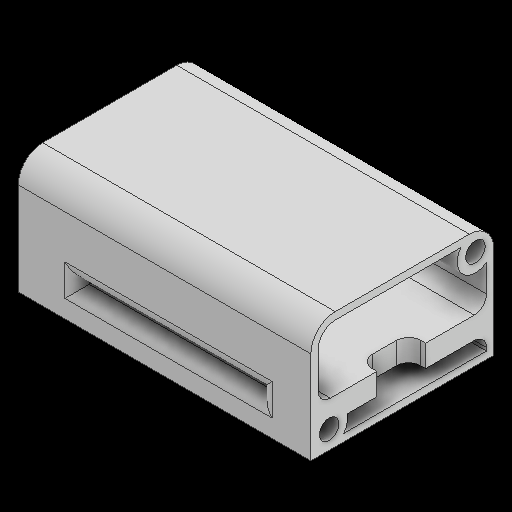
# Autodesk Inventor part: Gehäuse2
Saved by Autodesk Inventor 2027.1 (Build 311270010, 270A)
## iProperties
Created: 2026-10-15
Part Number: Gehäuse2
Material: Generisch
Document SubType Name: Modeling
Designer: josia
Density: 1 g/cm^3
Appearance: Vorgabe
Author: josia
Autodesk Inventor part; units mm, degrees
ref_plane "YZ Plane" through (0, 0, 0) normal (1, 0, 0) x (0, 1, 0)
ref_plane "XZ Plane" through (0, 0, 0) normal (0, 1, 0) x (-1, 0, 0)
ref_plane "XY Plane" through (0, 0, 0) normal (0, 0, 1) x (1, 0, 0)
sketch "Skizze1" plane through (0, 0, 0) normal (1, 0, 0) x (0, 1, 0)
  line L0 (-0.6, -15) -> (0.6, -15)
  line L1 (0.6, -15) -> (0.6, 15)
  line L2 (0.6, 15) -> (-0.6, 15)
  line L3 (-0.6, 15) -> (-0.6, -15)
  line L4 (-0.6, -15) -> (0.6, 15) construction
  line L5 (0.6, -15) -> (-0.6, 15) construction
  line L6 (0.6, 15) -> (14.6, 15)
  line L7 (18.6, 11) -> (18.6, 13.8)
  line L8 (18.6, 13.8) -> (0.6, 13.8)
  line L9 (0.6, 13.8) -> (0.6, 15)
  line L10 (0.6, -15) -> (14.6, -15)
  line L11 (18.6, -11) -> (18.6, -13.8)
  line L12 (18.6, -13.8) -> (0.6, -13.8)
  line L13 (0.6, -13.8) -> (0.6, -15)
  line L14 (18.6, 13.8) -> (17.4, 13.8)
  line L15 (17.4, 13.8) -> (17.4, -13.8)
  line L16 (17.4, -13.8) -> (18.6, -13.8)
  line L17 (18.6, -13.8) -> (18.6, 13.8)
  arc A0 (18.6, 11) -> (14.6, 15) centre (14.6, 11) ccw
  arc A1 (14.6, -15) -> (18.6, -11) centre (14.6, -11) ccw
  arc A2 (17.4, 11) -> (14.6, 13.8) centre (14.6, 11) ccw
  arc A3 (14.6, -13.8) -> (17.4, -11) centre (14.6, -11) ccw
  line L18 (0.6, 13.8) -> (3.1, 13.8)
  line L19 (3.1, 13.8) -> (3.1, -13.8)
  line L20 (3.1, -13.8) -> (0.6, -13.8)
  line L21 (0.6, -13.8) -> (0.6, 13.8)
  line L22 (3.1, 13.8) -> (6.7, 13.8)
  line L23 (6.7, 13.8) -> (6.7, -13.8)
  line L24 (6.7, -13.8) -> (3.1, -13.8)
  line L25 (3.1, -13.8) -> (3.1, 13.8)
  point P0 (0, 0)
  point P1 (18.6, 15)
  point P2 (18.6, -15)
  point P3 (0.6, -13.8)
  point P4 (0.6, 13.8)
  dimension "d0" = 1.2
  dimension "d1" = 30
  dimension "d2" = 18
  dimension "d3" = 1.2
  dimension "d4" = 18
  dimension "d5" = 1.2
  dimension "d6" = 1.2
  dimension "d7" = 4
  dimension "d8" = 4
  dimension "d9" = 2.5
  dimension "d10" = 3.6
  constraints: 52 end point, 12 parallel, 11 point on line, 8 point on circle, 8 tangent, 6 horizontal, 6 perpendicular, 4 centre point, 2 midpoint
  measures "d0" distance of L2.end L1.end
  measures "d1" distance of L1.end L0.end
  measures "d2" distance of L7.end L8.end
  measures "d3" distance of point (18.6, 15) L7.end
  measures "d4" distance of L12.end L11.end
  measures "d5" distance of L11.end point (18.6, -15)
  measures "d6" distance of L16.end L15.end
  measures "d7" radius of A0
  measures "d8" radius of A1
  measures "d9" distance of L19.end L20.end
  measures "d10" distance of L23.end L24.end
extrude "Extrusion1" add sketch "Skizze1" along normal blind 48 contours L3 L2 L1 L0 | L1 L12 A1 L10 | L6 A0 L8 L1 | L19 L8 L23 L12 | L12 L15 L8 A0 L17 A1 | L12 A3 L15 | L15 A2 L8
sketch "Skizze2" plane through (0, 0, 0) normal (-1, 0, 0) x (0, 0, 1)
  line L0 (-15, -0.6) -> (-15, 14.6) projected
  arc A0 (-11, 18.6) -> (-15, 14.6) centre (-11, 14.6) ccw projected
  line L1 (-11, 18.6) -> (11, 18.6) projected
  arc A1 (15, 14.6) -> (11, 18.6) centre (11, 14.6) ccw projected
  line L2 (15, 14.6) -> (15, -0.6) projected
  line L3 (15, -0.6) -> (-15, -0.6) projected
  point P0 (0, 0)
extrude "Extrusion2" add sketch "Skizze2" against normal blind 1.2
sketch "Skizze3" plane through (48, 0, 0) normal (1, 0, 0) x (0, 0, -1)
  line L0 (-13.8, 3.1) -> (13.8, 3.1) projected
  line L1 (13.8, 6.7) -> (-13.8, 6.7) projected
  line L2 (-4.1636, 3.1) -> (3.8364, 3.1)
  line L3 (3.8364, 3.1) -> (3.8364, 6.7)
  line L4 (3.8364, 6.7) -> (-4.1636, 6.7)
  line L5 (-4.1636, 6.7) -> (-4.1636, 3.1)
  point P0 (0, 0)
  dimension "d15" = 8
  constraints: 8 end point, 2 parallel, 2 point on line, 1 horizontal, 1 perpendicular
  measures "d15" distance of L4.end L3.end
extrude "Extrusion3" cut sketch "Skizze3" against normal blind 2.8
fillet "Rundung1" radius 2 2 edges at (45.2, 4.9, 4.1636) (45.2, 4.9, -3.8364)
sketch "Skizze4" plane through (0, -0.6, -15) normal (0, 0, -1) x (-1, 0, 0)
  line L0 (0, 0) -> (-48, 0) projected
  line L1 (0, 0) -> (0, 15.2) projected
  line L2 (-48, 0) -> (0, 0)
  line L3 (0, 0) -> (0, 4.9)
  line L4 (0, 4.9) -> (-48, 4.9)
  line L5 (-48, 4.9) -> (-48, 0)
  line L6 (-48, 4.9) -> (0, 4.9)
  line L7 (0, 4.9) -> (0, 6.1)
  line L8 (0, 6.1) -> (-48, 6.1)
  line L9 (-48, 6.1) -> (-48, 4.9)
  line L10 (-39.6501, 4.9) -> (-9.6501, 4.9)
  line L11 (-9.6501, 4.9) -> (-9.6501, 6.1)
  line L12 (-9.6501, 6.1) -> (-39.6501, 6.1)
  line L13 (-39.6501, 6.1) -> (-39.6501, 4.9)
  point P0 (0, 0.6)
  dimension "d19" = 4.9
  dimension "d20" = 1.2
  dimension "d21" = 30
  constraints: 24 end point, 6 parallel, 4 point on line, 3 horizontal, 3 perpendicular
  measures "d19" distance of L3.end L2.end
  measures "d20" distance of L7.end L6.end
  measures "d21" distance of L12.end L11.end
extrude "Extrusion4" cut sketch "Skizze4" against normal blind 52.7 contours L4 L13 L8 L11
fillet "Rundung2" radius 2 12 edges at (24.6501, 5.5, 15) (24.6501, 4.3, 15) (39.6501, 4.9, 15) (9.6501, 4.9, 15) (24.6501, 5.5, -15) (9.6501, 4.9, -15) (24.6501, 4.3, -15) (39.6501, 4.9, -15) (24.6, 3.1, -13.8) (24.6, 6.7, -13.8) (24.6, 6.7, 13.8) (24.6, 3.1, 13.8)
sketch "Skizze5" plane through (48, 0, 0) normal (1, 0, 0) x (0, 0, -1)
  line L0 (-15, -0.6) -> (15, -0.6) projected
  line L1 (-15, -0.6) -> (-12, -0.6)
  line L2 (-12, -0.6) -> (-12, 2.4)
  line L3 (-12, 2.4) -> (-15, 2.4)
  line L4 (-15, 2.4) -> (-15, -0.6)
  circle A0 centre (-12, 2.4) radius 3
  point P0 (0, 0)
  dimension "d25" = 3
  dimension "d26" = 3
  constraints: 8 end point, 2 parallel, 1 coincident, 1 horizontal, 1 horizontal alignment, 1 perpendicular, 2 other
  measures "d25" distance of L3.end L2.end
  measures "d26" distance of L2.end L1.end
extrude "Extrusion5" add sketch "Skizze5" against normal blind 4 contours A0 L3 L2 | L2 L3 A0
sketch "Skizze6" plane through (48, 0, 0) normal (1, 0, 0) x (0, 0, -1)
  line L0 (15, 18.6) -> (12, 18.6)
  line L1 (12, 18.6) -> (12, 15.6)
  line L2 (12, 15.6) -> (15, 15.6)
  line L3 (15, 15.6) -> (15, 18.6)
  circle A0 centre (12, 15.6) radius 3
  arc A1 (15, 14.6) -> (11, 18.6) centre (11, 14.6) ccw projected
  point P0 (0, 0)
  point P1 (11.5361, 18.5639)
  point P2 (14.9639, 15.1361)
  dimension "d29" = 3
  dimension "d30" = 3
  constraints: 8 end point, 2 parallel, 1 coincident, 1 horizontal, 1 perpendicular, 3 other
  measures "d29" distance of L2.end L1.end
  measures "d30" distance of L1.end L0.end
extrude "Extrusion6" add sketch "Skizze6" against normal blind 4 contours A1 L2 L1 | L1 L2 A1 A0 picked at (11.5596, 17.4909)
sketch "Skizze7" plane through (48, 0, 0) normal (1, 0, 0) x (0, 0, -1)
  arc A0 (-9.6, 0.6) -> (-9.0828, 3.1) centre (-12, 2.4) ccw projected
  circle A1 centre (-12, 2.4) radius 1.6
  arc A2 (9.6, 17.4) -> (13.8, 13.2) centre (12, 15.6) ccw projected
  circle A3 centre (12, 15.6) radius 1.6
  point P0 (0, 0)
  dimension "d33" = 3.2
  dimension "d34" = 3.2
  constraints: 2 centre point, 2 coincident
  measures "d33" diameter of A1
  measures "d34" diameter of A3
extrude "Extrusion7" cut sketch "Skizze7" against normal blind 2.5
sketch "Skizze8" plane through (0, -0.6, -15) normal (0, -1, 0) x (1, 0, 0)
  line L0 (0, 0) -> (48, 0) projected
  line L1 (48, 30) -> (48, 0) projected
  line L2 (0, 30) -> (48, 30) projected
  line L3 (0, 30) -> (0, 0) projected
  line L4 (48, 30) -> (0, 0)
  line L5 (48, 0) -> (0, 30)
  line L6 (11.25, 23.85) -> (36.75, 23.85)
  line L7 (36.75, 23.85) -> (36.75, 6.15)
  line L8 (36.75, 6.15) -> (11.25, 6.15)
  line L9 (11.25, 6.15) -> (11.25, 23.85)
  line L10 (11.25, 23.85) -> (36.75, 6.15) construction
  line L11 (36.75, 23.85) -> (11.25, 6.15) construction
  point P0 (0, 15)
  point P1 (24, 15)
  dimension "d37" = 25.5
  dimension "d38" = 17.7
  constraints: 16 end point, 3 midpoint, 2 parallel, 1 horizontal, 1 perpendicular
  measures "d37" distance of L7.end L8.end
  measures "d38" distance of L6.end L7.end
extrude "Extrusion8" cut sketch "Skizze8" against normal blind 2.75 contours L9 L5 L4 | L4 L5 L7 L8 L9 | L5 L4 L7 | L9 L6 L7 L4 L5
